Autodesk Fusion 360 part; units mm, degrees
(part 2 of 6)
sketch "PLACE - STUD R ROOM" plane through (0, 0, 2340.24) normal (0, 0, 1) x (1, 0, 0) in component "610201 AIR - SOFFIT"
  point P0 (578, -296)
  dimension "d10143" = 578
  dimension "d10144" = 296
  measures "d10143" horizontal distance of origin P0
  measures "d10144" vertical distance of origin P0
sketch "OUTLINE - HINGE ENVELOPE" plane through (0, 0, 0) normal (0, 0, 1) x (1, 0, 0) in component "618105 AIR - SOFFIT UNDERSIDE HINGE - HOLD"
  line L0 (0, 0) -> (60, 0)
  line L1 (60, 0) -> (60, 5)
  line L2 (60, 5) -> (0, 5)
  line L3 (0, 5) -> (0, 0)
  dimension "d10149" = 60
  dimension "d10150" = 5
  constraint horizontal L0
  constraint vertical L1
  constraint horizontal L2
  constraint vertical L3
  constraint vertical L0.start L3.end
  constraint horizontal L0.start L3.end
  measures "d10149" horizontal distance of L0.start L0.end
  measures "d10150" vertical distance of L0.start L2.end
extrude "EXTRUDE - HINGE ENVELOPE" add sketch "OUTLINE - HINGE ENVELOPE" along normal blind 8 separate body makes body 27 in component "618105 AIR - SOFFIT UNDERSIDE HINGE - HOLD"
ref_plane "WorkPlane5" through (0, 0, 2132) normal (0, 0, 1) x (1, 0, 0) in component "610201 AIR - SOFFIT"
sketch "PLACE - SOFFIT UNDERSIDE LEFT HINGE 1" plane through (0, 0, 2132) normal (0, 0, 1) x (1, 0, 0) in component "610201 AIR - SOFFIT"
  point P0 (-901, -641.14)
  dimension "d10155" = 901
  dimension "d10156" = 641.14
  measures "d10155" horizontal distance of origin P0
  measures "d10156" vertical distance of origin P0
ref_plane "WorkPlane6" through (0, 0, 2132) normal (0, 0, 1) x (1, 0, 0) in component "610201 AIR - SOFFIT"
sketch "PLACE - SOFFIT UNDERSIDE LEFT HINGE 3" plane through (0, 0, 2132) normal (0, 0, 1) x (1, 0, 0) in component "610201 AIR - SOFFIT"
  point P0 (-321, -641.14)
  dimension "d10163" = 321
  dimension "d10164" = 641.14
  measures "d10163" horizontal distance of origin P0
  measures "d10164" vertical distance of origin P0
ref_plane "WorkPlane7" through (0, 0, 2132) normal (0, 0, 1) x (1, 0, 0) in component "610201 AIR - SOFFIT"
sketch "PLACE - SOFFIT UNDERSIDE RIGHT HINGE 1" plane through (0, 0, 2132) normal (0, 0, 1) x (1, 0, 0) in component "610201 AIR - SOFFIT"
  point P0 (207.75, -641.14)
  dimension "d10171" = 207.75
  dimension "d10172" = 641.14
  measures "d10171" horizontal distance of origin P0
  measures "d10172" vertical distance of origin P0
ref_plane "WorkPlane8" through (0, 0, 2132) normal (0, 0, 1) x (1, 0, 0) in component "610201 AIR - SOFFIT"
sketch "PLACE - SOFFIT UNDERSIDE RIGHT HINGE 3" plane through (0, 0, 2132) normal (0, 0, 1) x (1, 0, 0) in component "610201 AIR - SOFFIT"
  point P0 (681.25, -641.14)
  dimension "d10179" = 681.25
  dimension "d10180" = 641.14
  measures "d10179" horizontal distance of origin P0
  measures "d10180" vertical distance of origin P0
sketch "OUTLINE - LATCH ENVELOPE" plane through (0, 0, 0) normal (0, 0, 1) x (1, 0, 0) in component "618106 AIR - SOFFIT UNDERSIDE LATCH - HOLD"
  line L0 (0, 0) -> (30, 0)
  line L1 (30, 0) -> (30, 8)
  line L2 (30, 8) -> (0, 8)
  line L3 (0, 8) -> (0, 0)
  dimension "d10185" = 30
  dimension "d10186" = 8
  constraint horizontal L0
  constraint vertical L1
  constraint horizontal L2
  constraint vertical L3
  constraint vertical L0.start L3.end
  constraint horizontal L0.start L3.end
  measures "d10185" horizontal distance of L0.start L0.end
  measures "d10186" vertical distance of L0.start L2.end
extrude "EXTRUDE - LATCH ENVELOPE" add sketch "OUTLINE - LATCH ENVELOPE" along normal blind 8 separate body makes body 28 in component "618106 AIR - SOFFIT UNDERSIDE LATCH - HOLD"
ref_plane "WorkPlane9" through (0, 0, 2132) normal (0, 0, 1) x (1, 0, 0) in component "610201 AIR - SOFFIT"
sketch "PLACE - SOFFIT UNDERSIDE LEFT LATCH 1" plane through (0, 0, 2132) normal (0, 0, 1) x (1, 0, 0) in component "610201 AIR - SOFFIT"
  point P0 (-886, -305)
  dimension "d10191" = 886
  dimension "d10192" = 305
  measures "d10191" horizontal distance of origin P0
  measures "d10192" vertical distance of origin P0
ref_plane "WorkPlane10" through (0, 0, 2132) normal (0, 0, 1) x (1, 0, 0) in component "610201 AIR - SOFFIT"
sketch "PLACE - SOFFIT UNDERSIDE LEFT LATCH 3" plane through (0, 0, 2132) normal (0, 0, 1) x (1, 0, 0) in component "610201 AIR - SOFFIT"
  point P0 (-306, -305)
  dimension "d10199" = 306
  dimension "d10200" = 305
  measures "d10199" horizontal distance of origin P0
  measures "d10200" vertical distance of origin P0
ref_plane "WorkPlane11" through (0, 0, 2132) normal (0, 0, 1) x (1, 0, 0) in component "610201 AIR - SOFFIT"
sketch "PLACE - SOFFIT UNDERSIDE RIGHT LATCH 1" plane through (0, 0, 2132) normal (0, 0, 1) x (1, 0, 0) in component "610201 AIR - SOFFIT"
  point P0 (222.75, -305)
  dimension "d10207" = 222.75
  dimension "d10208" = 305
  measures "d10207" horizontal distance of origin P0
  measures "d10208" vertical distance of origin P0
ref_plane "WorkPlane12" through (0, 0, 2132) normal (0, 0, 1) x (1, 0, 0) in component "610201 AIR - SOFFIT"
sketch "PLACE - SOFFIT UNDERSIDE RIGHT LATCH 3" plane through (0, 0, 2132) normal (0, 0, 1) x (1, 0, 0) in component "610201 AIR - SOFFIT"
  point P0 (696.25, -305)
  dimension "d10215" = 696.25
  dimension "d10216" = 305
  measures "d10215" horizontal distance of origin P0
  measures "d10216" vertical distance of origin P0
sketch "OUTLINE - LOCK SCREW" plane through (0, 0, 0) normal (0, 0, 1) x (1, 0, 0) in component "838002 HARDWARE - SOCKET HEAD BOLT - M6 X 25 - ISO 4762 8.8 ZINC"
  line L0 (0, 0) -> (10, 0)
  line L1 (10, 0) -> (10, 10)
  line L2 (10, 10) -> (0, 10)
  line L3 (0, 10) -> (0, 0)
  dimension "d10221" = 10
  dimension "d10222" = 10
  constraint horizontal L0
  constraint vertical L1
  constraint horizontal L2
  constraint vertical L3
  constraint vertical L0.start L3.end
  constraint horizontal L0.start L3.end
  measures "d10221" horizontal distance of L0.start L0.end
  measures "d10222" vertical distance of L0.start L2.end
extrude "EXTRUDE - LOCK SCREW" add sketch "OUTLINE - LOCK SCREW" along normal blind 6 separate body makes body 29 in component "838002 HARDWARE - SOCKET HEAD BOLT - M6 X 25 - ISO 4762 8.8 ZINC"
ref_plane "WorkPlane1" through (0, 0, 6) normal (0, 0, 1) x (1, 0, 0) in component "838002 HARDWARE - SOCKET HEAD BOLT - M6 X 25 - ISO 4762 8.8 ZINC"
sketch "OUTLINE - LOCK SCREW SHANK" plane through (0, 0, 6) normal (0, 0, 1) x (1, 0, 0) in component "838002 HARDWARE - SOCKET HEAD BOLT - M6 X 25 - ISO 4762 8.8 ZINC"
  circle A0 centre (5, 5) radius 3
  dimension "d10227" = 6
  dimension "d10228" = 5
  dimension "d10229" = 5
  measures "d10227" diameter of A0
  measures "d10228" horizontal distance of origin A0.centre
  measures "d10229" vertical distance of origin A0.centre
extrude "EXTRUDE - LOCK SCREW SHANK" add sketch "OUTLINE - LOCK SCREW SHANK" along normal blind 7 bodies 29 in component "838002 HARDWARE - SOCKET HEAD BOLT - M6 X 25 - ISO 4762 8.8 ZINC"
ref_plane "WorkPlane13" through (0, 0, 2340.24) normal (0, 0, 1) x (1, 0, 0) in component "610201 AIR - SOFFIT"
sketch "PLACE - LOCK SCREW 1" plane through (0, 0, 2340.24) normal (0, 0, 1) x (1, 0, 0) in component "610201 AIR - SOFFIT"
  point P0 (-1105, -296)
  dimension "d10234" = 1105
  dimension "d10235" = 296
  measures "d10234" horizontal distance of origin P0
  measures "d10235" vertical distance of origin P0
ref_plane "WorkPlane14" through (0, 0, 2340.24) normal (0, 0, 1) x (1, 0, 0) in component "610201 AIR - SOFFIT"
sketch "PLACE - LOCK SCREW 2" plane through (0, 0, 2340.24) normal (0, 0, 1) x (1, 0, 0) in component "610201 AIR - SOFFIT"
  point P0 (-955, -296)
  dimension "d10242" = 955
  dimension "d10243" = 296
  measures "d10242" horizontal distance of origin P0
  measures "d10243" vertical distance of origin P0
ref_plane "WorkPlane1" through (0, 0, 2159) normal (0, 0, 1) x (1, 0, 0) in component "611301 AIR - CARTRIDGE CASING (1)"
sketch "OUTLINE - CARTRIDGE EXHAUST" plane through (0, 0, 2159) normal (0, 0, 1) x (1, 0, 0) in component "611301 AIR - CARTRIDGE CASING (1)"
  line L0 (-883, -636.14) -> (867, -636.14)
  line L1 (867, -636.14) -> (867, -322.14)
  line L2 (867, -322.14) -> (-883, -322.14)
  line L3 (-883, -322.14) -> (-883, -636.14)
  dimension "d10250" = 1750
  dimension "d10252" = 883
  dimension "d10253" = 636.14
  constraint horizontal L0
  constraint vertical L1
  constraint horizontal L2
  constraint vertical L3
  measures "d10250" horizontal distance of L0.start L0.end
  measures "d10252" horizontal distance of origin L0.start
  measures "d10253" vertical distance of origin L0.start
extrude "EXTRUDE - CARTRIDGE EXHAUST" add sketch "OUTLINE - CARTRIDGE EXHAUST" along normal blind 173 separate body makes body 30 in component "611301 AIR - CARTRIDGE CASING (1)"
shell "SHELL - CARTRIDGE EXHAUST CASING" thickness 2 removed faces 2 at (867, -531.4733, 2216.6667) at (-883, -426.8067, 2216.6667) on bodies 30 in component "611301 AIR - CARTRIDGE CASING (1)"
sketch "OUTLINE - LAYER 50 EXHAUST" plane through (0, 0, 0) normal (0, 0, 1) x (1, 0, 0) in component "611302 AIR - CARTRIDGE FILL - LAYER 50 (1)"
  line L0 (0, 0) -> (1750, 0)
  line L1 (1750, 0) -> (1750, 50)
  line L2 (1750, 50) -> (0, 50)
  line L3 (0, 50) -> (0, 0)
  dimension "d10257" = 1750
  dimension "d10258" = 50
  constraint horizontal L0
  constraint vertical L1
  constraint horizontal L2
  constraint vertical L3
  constraint vertical L0.start L3.end
  constraint horizontal L0.start L3.end
  measures "d10257" horizontal distance of L0.start L0.end
  measures "d10258" vertical distance of L0.start L2.end
extrude "EXTRUDE - LAYER 50 EXHAUST" add sketch "OUTLINE - LAYER 50 EXHAUST" along normal blind 169 separate body makes body 31 in component "611302 AIR - CARTRIDGE FILL - LAYER 50 (1)"
ref_plane "WorkPlane1" through (0, 0, 2161) normal (0, 0, 1) x (1, 0, 0) in component "610301 AIR - SPLITTER CARTRIDGE - COMMON (EXHAUST)"
sketch "PLACE - LAYER 1 EXHAUST" plane through (0, 0, 2161) normal (0, 0, 1) x (1, 0, 0) in component "610301 AIR - SPLITTER CARTRIDGE - COMMON (EXHAUST)"
  point P0 (-883, -634.14)
  dimension "d10263" = 883
  dimension "d10264" = 634.14
  measures "d10263" horizontal distance of origin P0
  measures "d10264" vertical distance of origin P0
ref_plane "WorkPlane2" through (0, 0, 2161) normal (0, 0, 1) x (1, 0, 0) in component "610301 AIR - SPLITTER CARTRIDGE - COMMON (EXHAUST)"
sketch "PLACE - LAYER 2 EXHAUST" plane through (0, 0, 2161) normal (0, 0, 1) x (1, 0, 0) in component "610301 AIR - SPLITTER CARTRIDGE - COMMON (EXHAUST)"
  point P0 (-883, -504.14)
  dimension "d10271" = 883
  dimension "d10272" = 504.14
  measures "d10271" horizontal distance of origin P0
  measures "d10272" vertical distance of origin P0
ref_plane "WorkPlane3" through (0, 0, 2161) normal (0, 0, 1) x (1, 0, 0) in component "610301 AIR - SPLITTER CARTRIDGE - COMMON (EXHAUST)"
sketch "PLACE - LAYER 3 EXHAUST" plane through (0, 0, 2161) normal (0, 0, 1) x (1, 0, 0) in component "610301 AIR - SPLITTER CARTRIDGE - COMMON (EXHAUST)"
  point P0 (-883, -374.14)
  dimension "d10279" = 883
  dimension "d10280" = 374.14
  measures "d10279" horizontal distance of origin P0
  measures "d10280" vertical distance of origin P0
ref_plane "WorkPlane1" through (0, 0, 2159) normal (0, 0, 1) x (1, 0, 0) in component "611401 AIR - FAN BOX CASING - EXHAUST"
sketch "OUTLINE - EXHAUST FAN BOX" plane through (0, 0, 2159) normal (0, 0, 1) x (1, 0, 0) in component "611401 AIR - FAN BOX CASING - EXHAUST"
  line L0 (867, -636.14) -> (1161, -636.14)
  line L1 (1161, -636.14) -> (1161, -322.14)
  line L2 (1161, -322.14) -> (867, -322.14)
  line L3 (867, -322.14) -> (867, -636.14)
  dimension "d10287" = 294
  dimension "d10289" = 867
  dimension "d10290" = 636.14
  constraint horizontal L0
  constraint vertical L1
  constraint horizontal L2
  constraint vertical L3
  measures "d10287" horizontal distance of L0.start L0.end
  measures "d10289" horizontal distance of origin L0.start
  measures "d10290" vertical distance of origin L0.start
extrude "EXTRUDE - EXHAUST FAN BOX" add sketch "OUTLINE - EXHAUST FAN BOX" along normal blind 173 separate body makes body 32 in component "611401 AIR - FAN BOX CASING - EXHAUST"
shell "SHELL - EXHAUST FAN BOX (OPEN WHERE THE AIR PASSES)" thickness 3 removed faces 2 at (867, -426.8067, 2216.6667) at (965, -426.8067, 2332) on bodies 32 in component "611401 AIR - FAN BOX CASING - EXHAUST"
ref_plane "WorkPlane1" through (0, 0, 2330) normal (0, 0, 1) x (1, 0, 0) in component "611403 AIR - FAN BOX BULKHEAD - EXHAUST"
sketch "OUTLINE - FAN BOX BULKHEAD EXHAUST" plane through (0, 0, 2330) normal (0, 0, 1) x (1, 0, 0) in component "611403 AIR - FAN BOX BULKHEAD - EXHAUST"
  line L0 (867, -633.14) -> (1158, -633.14)
  line L1 (1158, -633.14) -> (1158, -325.14)
  line L2 (1158, -325.14) -> (867, -325.14)
  line L3 (867, -325.14) -> (867, -633.14)
  dimension "d10296" = 291
  dimension "d10298" = 867
  dimension "d10299" = 633.14
  constraint horizontal L0
  constraint vertical L1
  constraint horizontal L2
  constraint vertical L3
  measures "d10296" horizontal distance of L0.start L0.end
  measures "d10298" horizontal distance of origin L0.start
  measures "d10299" vertical distance of origin L0.start
extrude "EXTRUDE - FAN BOX BULKHEAD EXHAUST" add sketch "OUTLINE - FAN BOX BULKHEAD EXHAUST" along normal blind 2 separate body makes body 33 in component "611403 AIR - FAN BOX BULKHEAD - EXHAUST"
sketch "OUTLINE - FAN BOX LINING EXHAUST SIDE" plane through (0, 0, 0) normal (0, 0, 1) x (1, 0, 0) in component "611405 AIR - FAN BOX LINING - EXHAUST SIDE"
  line L0 (0, 0) -> (291, 0)
  line L1 (291, 0) -> (291, 50)
  line L2 (291, 50) -> (0, 50)
  line L3 (0, 50) -> (0, 0)
  dimension "d10302" = 291
  dimension "d10303" = 50
  constraint horizontal L0
  constraint vertical L1
  constraint horizontal L2
  constraint vertical L3
  constraint vertical L0.start L3.end
  constraint horizontal L0.start L3.end
  measures "d10302" horizontal distance of L0.start L0.end
  measures "d10303" vertical distance of L0.start L2.end
extrude "EXTRUDE - FAN BOX LINING EXHAUST SIDE" add sketch "OUTLINE - FAN BOX LINING EXHAUST SIDE" along normal blind 143 separate body makes body 34 in component "611405 AIR - FAN BOX LINING - EXHAUST SIDE"
ref_plane "WorkPlane1" through (0, 0, 2162) normal (0, 0, 1) x (1, 0, 0) in component "610402 AIR - EXHAUST FAN BOX"
sketch "PLACE - FAN BOX LINING EXHAUST SIDE 1" plane through (0, 0, 2162) normal (0, 0, 1) x (1, 0, 0) in component "610402 AIR - EXHAUST FAN BOX"
  point P0 (867, -633.14)
  dimension "d10308" = 867
  dimension "d10309" = 633.14
  measures "d10308" horizontal distance of origin P0
  measures "d10309" vertical distance of origin P0
ref_plane "WorkPlane2" through (0, 0, 2162) normal (0, 0, 1) x (1, 0, 0) in component "610402 AIR - EXHAUST FAN BOX"
sketch "PLACE - FAN BOX LINING EXHAUST SIDE 2" plane through (0, 0, 2162) normal (0, 0, 1) x (1, 0, 0) in component "610402 AIR - EXHAUST FAN BOX"
  point P0 (867, -375.14)
  dimension "d10316" = 867
  dimension "d10317" = 375.14
  measures "d10316" horizontal distance of origin P0
  measures "d10317" vertical distance of origin P0
ref_plane "WorkPlane1" through (0, 0, 2162) normal (0, 0, 1) x (1, 0, 0) in component "611406 AIR - FAN BOX LINING - EXHAUST FAR END"
sketch "OUTLINE - FAN BOX LINING EXHAUST FAR END" plane through (0, 0, 2162) normal (0, 0, 1) x (1, 0, 0) in component "611406 AIR - FAN BOX LINING - EXHAUST FAR END"
  line L0 (1108, -583.14) -> (1158, -583.14)
  line L1 (1158, -583.14) -> (1158, -375.14)
  line L2 (1158, -375.14) -> (1108, -375.14)
  line L3 (1108, -375.14) -> (1108, -583.14)
  dimension "d10324" = 50
  dimension "d10325" = 208
  dimension "d10326" = 1108
  dimension "d10327" = 583.14
  constraint horizontal L0
  constraint vertical L1
  constraint horizontal L2
  constraint vertical L3
  measures "d10324" horizontal distance of L0.start L0.end
  measures "d10325" vertical distance of L0.start L2.end
  measures "d10326" horizontal distance of origin L0.start
  measures "d10327" vertical distance of origin L0.start
extrude "EXTRUDE - FAN BOX LINING EXHAUST FAR END" add sketch "OUTLINE - FAN BOX LINING EXHAUST FAR END" along normal blind 93 separate body makes body 35 in component "611406 AIR - FAN BOX LINING - EXHAUST FAR END"
sketch "OUTLINE - FAN 140 ENVELOPE" plane through (0, 0, 0) normal (0, 0, 1) x (1, 0, 0) in component "618401 AIR - FAN - NOCTUA NF-A14 INDUSTRIALPPC-3000 PWM"
  line L0 (-70, -70) -> (70, -70)
  line L1 (70, -70) -> (70, 70)
  line L2 (70, 70) -> (-70, 70)
  line L3 (-70, 70) -> (-70, -70)
  dimension "d10330" = 140
  dimension "d10331" = 140
  dimension "d10332" = 70
  dimension "d10333" = 70
  constraint horizontal L0
  constraint vertical L1
  constraint horizontal L2
  constraint vertical L3
  measures "d10330" horizontal distance of L0.start L0.end
  measures "d10331" vertical distance of L0.start L2.end
  measures "d10332" horizontal distance of origin L0.start
  measures "d10333" vertical distance of origin L0.start
extrude "EXTRUDE - FAN 140 ENVELOPE" add sketch "OUTLINE - FAN 140 ENVELOPE" along normal blind 25 separate body makes body 36 in component "618401 AIR - FAN - NOCTUA NF-A14 INDUSTRIALPPC-3000 PWM"
ref_plane "WorkPlane3" through (0, 0, 2305) normal (0, 0, 1) x (1, 0, 0) in component "610402 AIR - EXHAUST FAN BOX"
sketch "PLACE - EXHAUST FAN 1" plane through (0, 0, 2305) normal (0, 0, 1) x (1, 0, 0) in component "610402 AIR - EXHAUST FAN BOX"
  point P0 (939.75, -479.14)
  dimension "d10338" = 939.75
  dimension "d10339" = 479.14
  measures "d10338" horizontal distance of origin P0
  measures "d10339" vertical distance of origin P0
ref_plane "WorkPlane4" through (0, 0, 2305) normal (0, 0, 1) x (1, 0, 0) in component "610402 AIR - EXHAUST FAN BOX"
sketch "PLACE - EXHAUST FAN 2" plane through (0, 0, 2305) normal (0, 0, 1) x (1, 0, 0) in component "610402 AIR - EXHAUST FAN BOX"
  point P0 (1085.25, -479.14)
  dimension "d10346" = 1085.25
  dimension "d10347" = 479.14
  measures "d10346" horizontal distance of origin P0
  measures "d10347" vertical distance of origin P0
ref_plane "WorkPlane1" through (0, 0, 1650) normal (0, 0, 1) x (1, 0, 0) in component "611402 AIR - FAN BOX CASING - SUPPLY"
sketch "OUTLINE - SUPPLY FAN BOX" plane through (0, 0, 1650) normal (0, 0, 1) x (1, 0, 0) in component "611402 AIR - FAN BOX CASING - SUPPLY"
  line L0 (680, -819) -> (980, -819)
  line L1 (980, -819) -> (980, -664)
  line L2 (980, -664) -> (680, -664)
  line L3 (680, -664) -> (680, -819)
  dimension "d10354" = 300
  dimension "d10355" = 155
  dimension "d10356" = 680
  dimension "d10357" = 819
  constraint horizontal L0
  constraint vertical L1
  constraint horizontal L2
  constraint vertical L3
  measures "d10354" horizontal distance of L0.start L0.end
  measures "d10355" vertical distance of L0.start L2.end
  measures "d10356" horizontal distance of origin L0.start
  measures "d10357" vertical distance of origin L0.start
extrude "EXTRUDE - SUPPLY FAN BOX" add sketch "OUTLINE - SUPPLY FAN BOX" along normal blind 300 separate body makes body 37 in component "611402 AIR - FAN BOX CASING - SUPPLY"
shell "SHELL - SUPPLY FAN BOX (OPEN WHERE THE AIR PASSES)" thickness 3 removed faces 2 at (780, -767.3333, 1950) at (780, -767.3333, 1650) on bodies 37 in component "611402 AIR - FAN BOX CASING - SUPPLY"
ref_plane "WorkPlane1" through (0, 0, 1698) normal (0, 0, 1) x (1, 0, 0) in component "611404 AIR - FAN BOX BULKHEAD - SUPPLY"
sketch "OUTLINE - FAN BOX BULKHEAD SUPPLY" plane through (0, 0, 1698) normal (0, 0, 1) x (1, 0, 0) in component "611404 AIR - FAN BOX BULKHEAD - SUPPLY"
  line L0 (683, -816) -> (977, -816)
  line L1 (977, -816) -> (977, -667)
  line L2 (977, -667) -> (683, -667)
  line L3 (683, -667) -> (683, -816)
  dimension "d10363" = 294
  dimension "d10364" = 149
  dimension "d10365" = 683
  dimension "d10366" = 816
  constraint horizontal L0
  constraint vertical L1
  constraint horizontal L2
  constraint vertical L3
  measures "d10363" horizontal distance of L0.start L0.end
  measures "d10364" vertical distance of L0.start L2.end
  measures "d10365" horizontal distance of origin L0.start
  measures "d10366" vertical distance of origin L0.start
extrude "EXTRUDE - FAN BOX BULKHEAD SUPPLY" add sketch "OUTLINE - FAN BOX BULKHEAD SUPPLY" along normal blind 2 separate body makes body 38 in component "611404 AIR - FAN BOX BULKHEAD - SUPPLY"
sketch "OUTLINE - FAN BOX LINING SUPPLY END" plane through (0, 0, 0) normal (0, 0, 1) x (1, 0, 0) in component "611407 AIR - FAN BOX LINING - SUPPLY END"
  line L0 (0, 0) -> (50, 0)
  line L1 (50, 0) -> (50, 149)
  line L2 (50, 149) -> (0, 149)
  line L3 (0, 149) -> (0, 0)
  dimension "d10369" = 50
  dimension "d10370" = 149
  constraint horizontal L0
  constraint vertical L1
  constraint horizontal L2
  constraint vertical L3
  constraint vertical L0.start L3.end
  constraint horizontal L0.start L3.end
  measures "d10369" horizontal distance of L0.start L0.end
  measures "d10370" vertical distance of L0.start L2.end
extrude "EXTRUDE - FAN BOX LINING SUPPLY END" add sketch "OUTLINE - FAN BOX LINING SUPPLY END" along normal blind 155 separate body makes body 39 in component "611407 AIR - FAN BOX LINING - SUPPLY END"
ref_plane "WorkPlane1" through (0, 0, 1795) normal (0, 0, 1) x (1, 0, 0) in component "610401 AIR - SUPPLY FAN BOX"
sketch "PLACE - FAN BOX LINING SUPPLY END 1" plane through (0, 0, 1795) normal (0, 0, 1) x (1, 0, 0) in component "610401 AIR - SUPPLY FAN BOX"
  point P0 (683, -816)
  dimension "d10375" = 683
  dimension "d10376" = 816
  measures "d10375" horizontal distance of origin P0
  measures "d10376" vertical distance of origin P0
ref_plane "WorkPlane2" through (0, 0, 1795) normal (0, 0, 1) x (1, 0, 0) in component "610401 AIR - SUPPLY FAN BOX"
sketch "PLACE - FAN BOX LINING SUPPLY END 2" plane through (0, 0, 1795) normal (0, 0, 1) x (1, 0, 0) in component "610401 AIR - SUPPLY FAN BOX"
  point P0 (927, -816)
  dimension "d10383" = 927
  dimension "d10384" = 816
  measures "d10383" horizontal distance of origin P0
  measures "d10384" vertical distance of origin P0
sketch "SECTION - FAN BOX LIP ANGLE SUPPLY" plane through (0, 0, 0) normal (1, 0, 0) x (0, 0, -1) in component "611408 AIR - FAN BOX LIP ANGLE - SUPPLY"
  line L0 (-1655, -845) -> (-1655, -819)
  line L1 (-1655, -819) -> (-1695, -819)
  line L2 (-1695, -819) -> (-1695, -822)
  line L3 (-1695, -822) -> (-1658, -822)
  line L4 (-1658, -822) -> (-1658, -845)
  line L5 (-1658, -845) -> (-1655, -845)
  point P0 (4000, -4000)
  dimension "d10389" = 4000
  dimension "d10390" = 4000
  dimension "d10391" = 5655
  dimension "d10392" = 5695
  dimension "d10393" = 5658
  dimension "d10394" = 3181
  dimension "d10395" = 3178
  dimension "d10396" = 3155
  constraint vertical L0
  constraint vertical L2
  constraint vertical L4
  constraint horizontal L1
  constraint horizontal L3
  constraint horizontal L5
  measures "d10389" horizontal distance of origin P0
  measures "d10390" vertical distance of origin P0
  measures "d10391" horizontal distance of L0.start P0
  measures "d10392" horizontal distance of L1.end P0
  measures "d10393" horizontal distance of L3.end P0
  measures "d10394" vertical distance of L0.end P0
  measures "d10395" vertical distance of L2.end P0
  measures "d10396" vertical distance of L4.end P0
extrude "EXTRUDE - FAN BOX LIP ANGLE SUPPLY" add sketch "SECTION - FAN BOX LIP ANGLE SUPPLY" along normal blind 344.7 from surface at 680 separate body makes body 40 in component "611408 AIR - FAN BOX LIP ANGLE - SUPPLY"
sketch "OUTLINE - FAN BOX PAD" plane through (0, 0, 0) normal (0, 0, 1) x (1, 0, 0) in component "618402 AIR - FAN BOX PAD - SUPPLY - RUBBER 40 X 15 X 5 - HOLD"
  line L0 (0, 0) -> (40, 0)
  line L1 (40, 0) -> (40, 15)
  line L2 (40, 15) -> (0, 15)
  line L3 (0, 15) -> (0, 0)
  dimension "d10400" = 40
  dimension "d10401" = 15
  constraint horizontal L0
  constraint vertical L1
  constraint horizontal L2
  constraint vertical L3
  constraint vertical L0.start L3.end
  constraint horizontal L0.start L3.end
  measures "d10400" horizontal distance of L0.start L0.end
  measures "d10401" vertical distance of L0.start L2.end
extrude "EXTRUDE - FAN BOX PAD" add sketch "OUTLINE - FAN BOX PAD" along normal blind 5 separate body makes body 41 in component "618402 AIR - FAN BOX PAD - SUPPLY - RUBBER 40 X 15 X 5 - HOLD"
ref_plane "WorkPlane3" through (0, 0, 1650) normal (0, 0, 1) x (1, 0, 0) in component "610401 AIR - SUPPLY FAN BOX"
sketch "PLACE - FAN BOX PAD LEFT" plane through (0, 0, 1650) normal (0, 0, 1) x (1, 0, 0) in component "610401 AIR - SUPPLY FAN BOX"
  point P0 (685, -841.5)
  dimension "d10406" = 685
  dimension "d10407" = 841.5
  measures "d10406" horizontal distance of origin P0
  measures "d10407" vertical distance of origin P0
ref_plane "WorkPlane4" through (0, 0, 1650) normal (0, 0, 1) x (1, 0, 0) in component "610401 AIR - SUPPLY FAN BOX"
sketch "PLACE - FAN BOX PAD RIGHT" plane through (0, 0, 1650) normal (0, 0, 1) x (1, 0, 0) in component "610401 AIR - SUPPLY FAN BOX"
  point P0 (979.7, -841.5)
  dimension "d10414" = 979.7
  dimension "d10415" = 841.5
  measures "d10414" horizontal distance of origin P0
  measures "d10415" vertical distance of origin P0
ref_plane "WorkPlane1" through (0, 0, 834) normal (0, 0, 1) x (1, 0, 0) in component "618501 AIR - RISER BUFFER - RUBBER - M6 - HOLD"
sketch "OUTLINE - RISER BUFFER" plane through (0, 0, 834) normal (0, 0, 1) x (1, 0, 0) in component "618501 AIR - RISER BUFFER - RUBBER - M6 - HOLD"
  line L0 (984.35, -824) -> (1004.35, -824)
  line L1 (1004.35, -824) -> (1004.35, -803.76)
  line L2 (1004.35, -803.76) -> (984.35, -803.76)
  line L3 (984.35, -803.76) -> (984.35, -824)
  dimension "d10422" = 20
  dimension "d10423" = 20.24
  dimension "d10424" = 984.35
  dimension "d10425" = 824
  constraint horizontal L0
  constraint vertical L1
  constraint horizontal L2
  constraint vertical L3
  measures "d10422" horizontal distance of L0.start L0.end
  measures "d10423" vertical distance of L0.start L2.end
  measures "d10424" horizontal distance of origin L0.start
  measures "d10425" vertical distance of origin L0.start
extrude "EXTRUDE - RISER BUFFER" add sketch "OUTLINE - RISER BUFFER" along normal blind 20 separate body makes body 42 in component "618501 AIR - RISER BUFFER - RUBBER - M6 - HOLD"
ref_plane "WorkPlane5" through (0, 0, 1700) normal (0, 0, 1) x (1, 0, 0) in component "610401 AIR - SUPPLY FAN BOX"
sketch "PLACE - SUPPLY FAN 1" plane through (0, 0, 1700) normal (0, 0, 1) x (1, 0, 0) in component "610401 AIR - SUPPLY FAN BOX"
  point P0 (756.5, -741.5)
  dimension "d10430" = 756.5
  dimension "d10431" = 741.5
  measures "d10430" horizontal distance of origin P0
  measures "d10431" vertical distance of origin P0
ref_plane "WorkPlane6" through (0, 0, 1700) normal (0, 0, 1) x (1, 0, 0) in component "610401 AIR - SUPPLY FAN BOX"
sketch "PLACE - SUPPLY FAN 2" plane through (0, 0, 1700) normal (0, 0, 1) x (1, 0, 0) in component "610401 AIR - SUPPLY FAN BOX"
  point P0 (903.5, -741.5)
  dimension "d10438" = 903.5
  dimension "d10439" = 741.5
  measures "d10438" horizontal distance of origin P0
  measures "d10439" vertical distance of origin P0
sketch "SECTION - SUPPLY TRANSITION" plane through (0, 0, 0) normal (0, 0, 1) x (1, 0, 0) in component "618102 AIR - SUPPLY TRANSITION - HOLD"
  line L0 (680, -819) -> (1043.1104, -819)
  line L1 (1043.1104, -819) -> (1146, -726.5019)
  line L2 (1146, -726.5019) -> (1146, -646.5)
  line L3 (1146, -646.5) -> (680, -646.5)
  line L4 (680, -646.5) -> (680, -819)
  point P0 (-4000, -4000)
  dimension "d10444" = 4000
  dimension "d10445" = 4000
  dimension "d10447" = 5146
  dimension "d10448" = 4680
  dimension "d10449" = 3181
  dimension "d10451" = 3353.5
  constraint vertical L2
  constraint vertical L4
  constraint horizontal L0
  constraint horizontal L3
  measures "d10444" horizontal distance of origin P0
  measures "d10445" vertical distance of origin P0
  measures "d10447" horizontal distance of L1.end P0
  measures "d10448" horizontal distance of L3.end P0
  measures "d10449" vertical distance of L0.start P0
  measures "d10451" vertical distance of L2.end P0
extrude "EXTRUDE - SUPPLY TRANSITION" add sketch "SECTION - SUPPLY TRANSITION" along normal blind 152 from surface at 1950 separate body makes body 43 in component "618102 AIR - SUPPLY TRANSITION - HOLD"
sketch "SECTION - SUPPLY TRANSITION BESIDE THE BOX" plane through (0, 0, 0) normal (0, 0, 1) x (1, 0, 0) in component "618102 AIR - SUPPLY TRANSITION - HOLD"
  line L0 (980, -819) -> (1043.1104, -819)
  line L1 (1043.1104, -819) -> (1146, -726.5019)
  line L2 (1146, -726.5019) -> (1146, -646.5)
  line L3 (1146, -646.5) -> (980, -646.5)
  line L4 (980, -646.5) -> (980, -819)
  point P0 (-4000, -4000)
  dimension "d10455" = 4000
  dimension "d10456" = 4000
  dimension "d10458" = 5146
  dimension "d10459" = 4980
  dimension "d10460" = 3181
  dimension "d10462" = 3353.5
  constraint vertical L2
  constraint vertical L4
  constraint horizontal L0
  constraint horizontal L3
  measures "d10455" horizontal distance of origin P0
  measures "d10456" vertical distance of origin P0
  measures "d10458" horizontal distance of L1.end P0
  measures "d10459" horizontal distance of L3.end P0
  measures "d10460" vertical distance of L0.start P0
  measures "d10462" vertical distance of L2.end P0
extrude "JOIN - SUPPLY TRANSITION BESIDE THE BOX" add sketch "SECTION - SUPPLY TRANSITION BESIDE THE BOX" along normal blind 55 from surface at 1895 bodies 43 in component "618102 AIR - SUPPLY TRANSITION - HOLD"
ref_plane "WorkPlane1" through (0, 0, 252) normal (0, 0, 1) x (1, 0, 0) in component "611501 AIR - INTAKE RISER"
sketch "OUTLINE - INTAKE RISER" plane through (0, 0, 252) normal (0, 0, 1) x (1, 0, 0) in component "611501 AIR - INTAKE RISER"
  line L0 (959, -803) -> (1098, -803)
  line L1 (1098, -803) -> (1098, -653)
  line L2 (1098, -653) -> (959, -653)
  line L3 (959, -653) -> (959, -803)
  dimension "d10468" = 139
  dimension "d10469" = 150
  dimension "d10470" = 959
  dimension "d10471" = 803
  constraint horizontal L0
  constraint vertical L1
  constraint horizontal L2
  constraint vertical L3
  measures "d10468" horizontal distance of L0.start L0.end
  measures "d10469" vertical distance of L0.start L2.end
  measures "d10470" horizontal distance of origin L0.start
  measures "d10471" vertical distance of origin L0.start
extrude "EXTRUDE - INTAKE RISER" add sketch "OUTLINE - INTAKE RISER" along normal blind 1134 separate body makes body 44 in component "611501 AIR - INTAKE RISER"
sketch "SECTION - INTAKE RISER CHAMFER" plane through (0, 0, 0) normal (0, 0, 1) x (1, 0, 0) in component "611501 AIR - INTAKE RISER"
  line L0 (1090, -803) -> (1098, -803)
  line L1 (1098, -803) -> (1098, -795)
  line L2 (1098, -795) -> (1090, -803)
  point P0 (-4000, -4000)
  dimension "d10474" = 4000
  dimension "d10475" = 4000
  dimension "d10476" = 5090
  dimension "d10477" = 5098
  dimension "d10478" = 3197
  dimension "d10479" = 3205
  constraint vertical L1
  constraint horizontal L0
  measures "d10474" horizontal distance of origin P0
  measures "d10475" vertical distance of origin P0
  measures "d10476" horizontal distance of L0.start P0
  measures "d10477" horizontal distance of L0.end P0
  measures "d10478" vertical distance of L0.start P0
  measures "d10479" vertical distance of L1.end P0
extrude "CUT - INTAKE RISER CHAMFER" cut sketch "SECTION - INTAKE RISER CHAMFER" along normal blind 1136 from surface at 251 bodies 44 in component "611501 AIR - INTAKE RISER"
shell "SHELL - INTAKE RISER" thickness 1 removed faces 2 at (1005.3333, -750.3333, 1386) at (1005.3333, -750.3333, 252) on bodies 44 in component "611501 AIR - INTAKE RISER"
sketch "SECTION - RISER TRANSITION" plane through (0, 0, 0) normal (0, 1, 0) x (1, 0, 0) in component "618103 AIR - RISER TRANSITION - HOLD"
  line L0 (959, -1386) -> (1098, -1386)
  line L1 (1098, -1386) -> (980, -1650)
  line L2 (980, -1650) -> (680, -1650)
  line L3 (680, -1650) -> (959, -1386)
  point P0 (-4000, 4000)
  dimension "d10484" = 4000
  dimension "d10485" = 4000
  dimension "d10486" = 4959
  dimension "d10487" = 5098
  dimension "d10488" = 4980
  dimension "d10489" = 4680
  dimension "d10490" = 5386
  dimension "d10491" = 5650
  constraint horizontal L0
  constraint horizontal L2
  measures "d10484" horizontal distance of origin P0
  measures "d10485" vertical distance of origin P0
  measures "d10486" horizontal distance of L0.start P0
  measures "d10487" horizontal distance of L0.end P0
  measures "d10488" horizontal distance of L1.end P0
  measures "d10489" horizontal distance of L2.end P0
  measures "d10490" vertical distance of L0.start P0
  measures "d10491" vertical distance of L1.end P0
extrude "EXTRUDE - RISER TRANSITION" add sketch "SECTION - RISER TRANSITION" along normal blind 150 from surface at -803 separate body makes body 45 in component "618103 AIR - RISER TRANSITION - HOLD"
ref_plane "WorkPlane1" through (0, 0, 2332) normal (0, 0, 1) x (1, 0, 0) in component "611601 AIR - ROOF SLEEVE"
sketch "OUTLINE - ROOF SLEEVE" plane through (0, 0, 2332) normal (0, 0, 1) x (1, 0, 0) in component "611601 AIR - ROOF SLEEVE"
  line L0 (872, -620) -> (1157, -620)
  line L1 (1157, -620) -> (1157, -326)
  line L2 (1157, -326) -> (872, -326)
  line L3 (872, -326) -> (872, -620)
  dimension "d10497" = 285
  dimension "d10498" = 294
  dimension "d10499" = 872
  dimension "d10500" = 620
  constraint horizontal L0
  constraint vertical L1
  constraint horizontal L2
  constraint vertical L3
  measures "d10497" horizontal distance of L0.start L0.end
  measures "d10498" vertical distance of L0.start L2.end
  measures "d10499" horizontal distance of origin L0.start
  measures "d10500" vertical distance of origin L0.start
extrude "EXTRUDE - ROOF SLEEVE" add sketch "OUTLINE - ROOF SLEEVE" along normal blind 68 separate body makes body 46 in component "611601 AIR - ROOF SLEEVE"
shell "SHELL - ROOF SLEEVE" thickness 1 removed faces 2 at (967, -424, 2400) at (967, -424, 2332) on bodies 46 in component "611601 AIR - ROOF SLEEVE"
ref_plane "WorkPlane2" through (0, 0, 2400) normal (0, 0, 1) x (1, 0, 0) in component "611601 AIR - ROOF SLEEVE"
sketch "OUTLINE - ROOF SLEEVE FLANGE" plane through (0, 0, 2400) normal (0, 0, 1) x (1, 0, 0) in component "611601 AIR - ROOF SLEEVE"
  line L0 (832, -635) -> (1172, -635)
  line L1 (1172, -635) -> (1172, -253)
  line L2 (1172, -253) -> (832, -253)
  line L3 (832, -253) -> (832, -635)
  dimension "d10506" = 340
  dimension "d10507" = 382
  dimension "d10508" = 832
  dimension "d10509" = 635
  constraint horizontal L0
  constraint vertical L1
  constraint horizontal L2
  constraint vertical L3
  measures "d10506" horizontal distance of L0.start L0.end
  measures "d10507" vertical distance of L0.start L2.end
  measures "d10508" horizontal distance of origin L0.start
  measures "d10509" vertical distance of origin L0.start
extrude "JOIN - ROOF SLEEVE FLANGE" add sketch "OUTLINE - ROOF SLEEVE FLANGE" along normal blind 1 bodies 46 in component "611601 AIR - ROOF SLEEVE"
ref_plane "WorkPlane3" through (0, 0, 2400) normal (0, 0, 1) x (1, 0, 0) in component "611601 AIR - ROOF SLEEVE"
sketch "OUTLINE - ROOF SLEEVE FLANGE OPENING" plane through (0, 0, 2400) normal (0, 0, 1) x (1, 0, 0) in component "611601 AIR - ROOF SLEEVE"
  line L0 (873, -619) -> (1156, -619)
  line L1 (1156, -619) -> (1156, -327)
  line L2 (1156, -327) -> (873, -327)
  line L3 (873, -327) -> (873, -619)
  dimension "d10514" = 283
  dimension "d10515" = 292
  dimension "d10516" = 873
  dimension "d10517" = 619
  constraint horizontal L0
  constraint vertical L1
  constraint horizontal L2
  constraint vertical L3
  measures "d10514" horizontal distance of L0.start L0.end
  measures "d10515" vertical distance of L0.start L2.end
  measures "d10516" horizontal distance of origin L0.start
  measures "d10517" vertical distance of origin L0.start
extrude "CUT - ROOF SLEEVE FLANGE OPENING" cut sketch "OUTLINE - ROOF SLEEVE FLANGE OPENING" along normal blind 1 bodies 46 in component "611601 AIR - ROOF SLEEVE"
ref_plane "WorkPlane1" through (0, 0, 2401) normal (0, 0, 1) x (1, 0, 0) in component "611602 AIR - ROOF GRILLE"
sketch "OUTLINE - ROOF GRILLE" plane through (0, 0, 2401) normal (0, 0, 1) x (1, 0, 0) in component "611602 AIR - ROOF GRILLE"
  line L0 (832, -635) -> (1172, -635)
  line L1 (1172, -635) -> (1172, -253)
  line L2 (1172, -253) -> (832, -253)
  line L3 (832, -253) -> (832, -635)
  dimension "d10522" = 340
  dimension "d10523" = 382
  dimension "d10524" = 832
  dimension "d10525" = 635
  constraint horizontal L0
  constraint vertical L1
  constraint horizontal L2
  constraint vertical L3
  measures "d10522" horizontal distance of L0.start L0.end
  measures "d10523" vertical distance of L0.start L2.end
  measures "d10524" horizontal distance of origin L0.start
  measures "d10525" vertical distance of origin L0.start
extrude "EXTRUDE - ROOF GRILLE" add sketch "OUTLINE - ROOF GRILLE" along normal blind 2 separate body makes body 47 in component "611602 AIR - ROOF GRILLE"
ref_plane "WorkPlane2" through (0, -641.14, 0) normal (0, 1, 0) x (0, 0, 1) in component "611109 AIR - COLUMN CORNER ANGLE - BACK"
sketch "HOLE - COLUMN ANGLE BL FEATURE 1" plane through (0, -641.14, 0) normal (0, 1, 0) x (1, 0, 0) in component "611109 AIR - COLUMN CORNER ANGLE - BACK"
  circle A0 centre (971, -1690) radius 6
  dimension "d10530" = 12
  dimension "d10531" = 971
  dimension "d10532" = 1690
  measures "d10530" diameter of A0
  measures "d10531" horizontal distance of origin A0.centre
  measures "d10532" vertical distance of origin A0.centre
extrude "CUT - COLUMN ANGLE BL FEATURE 1" cut sketch "HOLE - COLUMN ANGLE BL FEATURE 1" along normal blind 2 bodies 12 in component "611109 AIR - COLUMN CORNER ANGLE - BACK"
ref_plane "WorkPlane3" through (0, 0, 1690) normal (0, 0, 1) x (1, 0, 0) in component "611109 AIR - COLUMN CORNER ANGLE - BACK"
sketch "OUTLINE - COLUMN ANGLE BL FEATURE 2" plane through (0, 0, 1690) normal (0, 0, 1) x (1, 0, 0) in component "611109 AIR - COLUMN CORNER ANGLE - BACK"
  line L0 (967.75, -641.14) -> (974.25, -641.14)
  line L1 (974.25, -641.14) -> (974.25, -639.14)
  line L2 (974.25, -639.14) -> (967.75, -639.14)
  line L3 (967.75, -639.14) -> (967.75, -641.14)
  dimension "d10537" = 6.5
  dimension "d10539" = 967.75
  dimension "d10540" = 641.14
  constraint horizontal L0
  constraint vertical L1
  constraint horizontal L2
  constraint vertical L3
  measures "d10537" horizontal distance of L0.start L0.end
  measures "d10539" horizontal distance of origin L0.start
  measures "d10540" vertical distance of origin L0.start
extrude "CUT - COLUMN ANGLE BL FEATURE 2" cut sketch "OUTLINE - COLUMN ANGLE BL FEATURE 2" along normal blind 10 bodies 12 in component "611109 AIR - COLUMN CORNER ANGLE - BACK"
ref_plane "WorkPlane4" through (0, -641.14, 0) normal (0, 1, 0) x (0, 0, 1) in component "611109 AIR - COLUMN CORNER ANGLE - BACK"
sketch "HOLE - COLUMN ANGLE BL FEATURE 3" plane through (0, -641.14, 0) normal (0, 1, 0) x (1, 0, 0) in component "611109 AIR - COLUMN CORNER ANGLE - BACK"
  circle A0 centre (971, -1700) radius 3.25
  dimension "d10545" = 6.5
  dimension "d10546" = 971
  dimension "d10547" = 1700
  measures "d10545" diameter of A0
  measures "d10546" horizontal distance of origin A0.centre
  measures "d10547" vertical distance of origin A0.centre
extrude "CUT - COLUMN ANGLE BL FEATURE 3" cut sketch "HOLE - COLUMN ANGLE BL FEATURE 3" along normal blind 2 bodies 12 in component "611109 AIR - COLUMN CORNER ANGLE - BACK"
ref_plane "WorkPlane5" through (0, -641.14, 0) normal (0, 1, 0) x (0, 0, 1) in component "611109 AIR - COLUMN CORNER ANGLE - BACK"
sketch "HOLE - COLUMN ANGLE BL FEATURE 4" plane through (0, -641.14, 0) normal (0, 1, 0) x (1, 0, 0) in component "611109 AIR - COLUMN CORNER ANGLE - BACK"
  circle A0 centre (971, -1840) radius 6
  dimension "d10552" = 12
  dimension "d10553" = 971
  dimension "d10554" = 1840
  measures "d10552" diameter of A0
  measures "d10553" horizontal distance of origin A0.centre
  measures "d10554" vertical distance of origin A0.centre
extrude "CUT - COLUMN ANGLE BL FEATURE 4" cut sketch "HOLE - COLUMN ANGLE BL FEATURE 4" along normal blind 2 bodies 12 in component "611109 AIR - COLUMN CORNER ANGLE - BACK"
ref_plane "WorkPlane6" through (0, 0, 1840) normal (0, 0, 1) x (1, 0, 0) in component "611109 AIR - COLUMN CORNER ANGLE - BACK"
sketch "OUTLINE - COLUMN ANGLE BL FEATURE 5" plane through (0, 0, 1840) normal (0, 0, 1) x (1, 0, 0) in component "611109 AIR - COLUMN CORNER ANGLE - BACK"
  line L0 (967.75, -641.14) -> (974.25, -641.14)
  line L1 (974.25, -641.14) -> (974.25, -639.14)
  line L2 (974.25, -639.14) -> (967.75, -639.14)
  line L3 (967.75, -639.14) -> (967.75, -641.14)
  dimension "d10559" = 6.5
  dimension "d10561" = 967.75
  dimension "d10562" = 641.14
  constraint horizontal L0
  constraint vertical L1
  constraint horizontal L2
  constraint vertical L3
  measures "d10559" horizontal distance of L0.start L0.end
  measures "d10561" horizontal distance of origin L0.start
  measures "d10562" vertical distance of origin L0.start
extrude "CUT - COLUMN ANGLE BL FEATURE 5" cut sketch "OUTLINE - COLUMN ANGLE BL FEATURE 5" along normal blind 10 bodies 12 in component "611109 AIR - COLUMN CORNER ANGLE - BACK"
ref_plane "WorkPlane7" through (0, -641.14, 0) normal (0, 1, 0) x (0, 0, 1) in component "611109 AIR - COLUMN CORNER ANGLE - BACK"
sketch "HOLE - COLUMN ANGLE BL FEATURE 6" plane through (0, -641.14, 0) normal (0, 1, 0) x (1, 0, 0) in component "611109 AIR - COLUMN CORNER ANGLE - BACK"
  circle A0 centre (971, -1850) radius 3.25
  dimension "d10567" = 6.5
  dimension "d10568" = 971
  dimension "d10569" = 1850
  measures "d10567" diameter of A0
  measures "d10568" horizontal distance of origin A0.centre
  measures "d10569" vertical distance of origin A0.centre
extrude "CUT - COLUMN ANGLE BL FEATURE 6" cut sketch "HOLE - COLUMN ANGLE BL FEATURE 6" along normal blind 2 bodies 12 in component "611109 AIR - COLUMN CORNER ANGLE - BACK"
ref_plane "WorkPlane2" through (0, 0, 0) normal (0, 0, 1) x (1, 0, 0) in component "611106 AIR - COLUMN FOOT PLATE"
sketch "HOLE - COLUMN FOOT PLATE FEATURE 7" plane through (0, 0, 0) normal (0, 0, 1) x (1, 0, 0) in component "611106 AIR - COLUMN FOOT PLATE"
  circle A0 centre (989, -605) radius 4.25
  dimension "d10574" = 8.5
  dimension "d10575" = 989
  dimension "d10576" = 605
  measures "d10574" diameter of A0
  measures "d10575" horizontal distance of origin A0.centre
  measures "d10576" vertical distance of origin A0.centre
extrude "CUT - COLUMN FOOT PLATE FEATURE 7" cut sketch "HOLE - COLUMN FOOT PLATE FEATURE 7" along normal blind 2 bodies 1 in component "611106 AIR - COLUMN FOOT PLATE"
ref_plane "WorkPlane3" through (0, 0, 0) normal (0, 0, 1) x (1, 0, 0) in component "611106 AIR - COLUMN FOOT PLATE"
sketch "OUTLINE - COLUMN FOOT PLATE FEATURE 8" plane through (0, 0, 0) normal (0, 0, 1) x (1, 0, 0) in component "611106 AIR - COLUMN FOOT PLATE"
  line L0 (1121.75, -339.75) -> (1130.25, -339.75)
  line L1 (1130.25, -339.75) -> (1130.25, -334.25)
  line L2 (1130.25, -334.25) -> (1121.75, -334.25)
  line L3 (1121.75, -334.25) -> (1121.75, -339.75)
  dimension "d10581" = 8.5
  dimension "d10582" = 5.5
  dimension "d10583" = 1121.75
  dimension "d10584" = 339.75
  constraint horizontal L0
  constraint vertical L1
  constraint horizontal L2
  constraint vertical L3
  measures "d10581" horizontal distance of L0.start L0.end
  measures "d10582" vertical distance of L0.start L2.end
  measures "d10583" horizontal distance of origin L0.start
  measures "d10584" vertical distance of origin L0.start
extrude "CUT - COLUMN FOOT PLATE FEATURE 8" cut sketch "OUTLINE - COLUMN FOOT PLATE FEATURE 8" along normal blind 2 bodies 1 in component "611106 AIR - COLUMN FOOT PLATE"
ref_plane "WorkPlane4" through (0, 0, 0) normal (0, 0, 1) x (1, 0, 0) in component "611106 AIR - COLUMN FOOT PLATE"
sketch "HOLE - COLUMN FOOT PLATE FEATURE 9" plane through (0, 0, 0) normal (0, 0, 1) x (1, 0, 0) in component "611106 AIR - COLUMN FOOT PLATE"
  circle A0 centre (1126, -339.75) radius 4.25
  dimension "d10589" = 8.5
  dimension "d10590" = 1126
  dimension "d10591" = 339.75
  measures "d10589" diameter of A0
  measures "d10590" horizontal distance of origin A0.centre
  measures "d10591" vertical distance of origin A0.centre
extrude "CUT - COLUMN FOOT PLATE FEATURE 9" cut sketch "HOLE - COLUMN FOOT PLATE FEATURE 9" along normal blind 2 bodies 1 in component "611106 AIR - COLUMN FOOT PLATE"
ref_plane "WorkPlane5" through (0, 0, 0) normal (0, 0, 1) x (1, 0, 0) in component "611106 AIR - COLUMN FOOT PLATE"
sketch "HOLE - COLUMN FOOT PLATE FEATURE 10" plane through (0, 0, 0) normal (0, 0, 1) x (1, 0, 0) in component "611106 AIR - COLUMN FOOT PLATE"
  circle A0 centre (1126, -334.25) radius 4.25
  dimension "d10596" = 8.5
  dimension "d10597" = 1126
  dimension "d10598" = 334.25
  measures "d10596" diameter of A0
  measures "d10597" horizontal distance of origin A0.centre
  measures "d10598" vertical distance of origin A0.centre
extrude "CUT - COLUMN FOOT PLATE FEATURE 10" cut sketch "HOLE - COLUMN FOOT PLATE FEATURE 10" along normal blind 2 bodies 1 in component "611106 AIR - COLUMN FOOT PLATE"
ref_plane "WorkPlane2" through (0, 0, 2346.24) normal (0, 0, 1) x (1, 0, 0) in component "611205 AIR - SOFFIT TOP RAIL - DOOR SIDE"
sketch "OUTLINE - SOFFIT RAIL DOOR FEATURE 11" plane through (0, 0, 2346.24) normal (0, 0, 1) x (1, 0, 0) in component "611205 AIR - SOFFIT TOP RAIL - DOOR SIDE"
  line L0 (-586.25, -641.14) -> (-579.75, -641.14)
  line L1 (-579.75, -641.14) -> (-579.75, -635)
  line L2 (-579.75, -635) -> (-586.25, -635)
  line L3 (-586.25, -635) -> (-586.25, -641.14)
  dimension "d10603" = 6.5
  dimension "d10604" = 6.14
  dimension "d10605" = 586.25
  dimension "d10606" = 641.14
  constraint horizontal L0
  constraint vertical L1
  constraint horizontal L2
  constraint vertical L3
  measures "d10603" horizontal distance of L0.start L0.end
  measures "d10604" vertical distance of L0.start L2.end
  measures "d10605" horizontal distance of origin L0.start
  measures "d10606" vertical distance of origin L0.start
extrude "CUT - SOFFIT RAIL DOOR FEATURE 11" cut sketch "OUTLINE - SOFFIT RAIL DOOR FEATURE 11" along normal blind 3 bodies 19 in component "611205 AIR - SOFFIT TOP RAIL - DOOR SIDE"
ref_plane "WorkPlane3" through (0, 0, 2346.24) normal (0, 0, 1) x (1, 0, 0) in component "611205 AIR - SOFFIT TOP RAIL - DOOR SIDE"
sketch "HOLE - SOFFIT RAIL DOOR FEATURE 12" plane through (0, 0, 2346.24) normal (0, 0, 1) x (1, 0, 0) in component "611205 AIR - SOFFIT TOP RAIL - DOOR SIDE"
  circle A0 centre (-583, -635) radius 3.25
  dimension "d10611" = 6.5
  dimension "d10612" = 583
  dimension "d10613" = 635
  measures "d10611" diameter of A0
  measures "d10612" horizontal distance of origin A0.centre
  measures "d10613" vertical distance of origin A0.centre
extrude "CUT - SOFFIT RAIL DOOR FEATURE 12" cut sketch "HOLE - SOFFIT RAIL DOOR FEATURE 12" along normal blind 3 bodies 19 in component "611205 AIR - SOFFIT TOP RAIL - DOOR SIDE"
ref_plane "WorkPlane2" through (0, 0, 2346.24) normal (0, 0, 1) x (1, 0, 0) in component "611209 AIR - SOFFIT TOP RAIL - ROOM SIDE"
sketch "OUTLINE - SOFFIT RAIL ROOM FEATURE 13" plane through (0, 0, 2346.24) normal (0, 0, 1) x (1, 0, 0) in component "611209 AIR - SOFFIT TOP RAIL - ROOM SIDE"
  line L0 (-586.25, -309) -> (-579.75, -309)
  line L1 (-579.75, -309) -> (-579.75, -291)
  line L2 (-579.75, -291) -> (-586.25, -291)
  line L3 (-586.25, -291) -> (-586.25, -309)
  dimension "d10618" = 6.5
  dimension "d10619" = 18
  dimension "d10620" = 586.25
  dimension "d10621" = 309
  constraint horizontal L0
  constraint vertical L1
  constraint horizontal L2
  constraint vertical L3
  measures "d10618" horizontal distance of L0.start L0.end
  measures "d10619" vertical distance of L0.start L2.end
  measures "d10620" horizontal distance of origin L0.start
  measures "d10621" vertical distance of origin L0.start
extrude "CUT - SOFFIT RAIL ROOM FEATURE 13" cut sketch "OUTLINE - SOFFIT RAIL ROOM FEATURE 13" along normal blind 3 bodies 20 in component "611209 AIR - SOFFIT TOP RAIL - ROOM SIDE"
ref_plane "WorkPlane3" through (0, 0, 2346.24) normal (0, 0, 1) x (1, 0, 0) in component "611209 AIR - SOFFIT TOP RAIL - ROOM SIDE"
sketch "HOLE - SOFFIT RAIL ROOM FEATURE 14" plane through (0, 0, 2346.24) normal (0, 0, 1) x (1, 0, 0) in component "611209 AIR - SOFFIT TOP RAIL - ROOM SIDE"
  circle A0 centre (-583, -291) radius 3.25
  dimension "d10626" = 6.5
  dimension "d10627" = 583
  dimension "d10628" = 291
  measures "d10626" diameter of A0
  measures "d10627" horizontal distance of origin A0.centre
  measures "d10628" vertical distance of origin A0.centre
extrude "CUT - SOFFIT RAIL ROOM FEATURE 14" cut sketch "HOLE - SOFFIT RAIL ROOM FEATURE 14" along normal blind 3 bodies 20 in component "611209 AIR - SOFFIT TOP RAIL - ROOM SIDE"
ref_plane "WorkPlane4" through (0, 0, 2346.24) normal (0, 0, 1) x (1, 0, 0) in component "611205 AIR - SOFFIT TOP RAIL - DOOR SIDE"